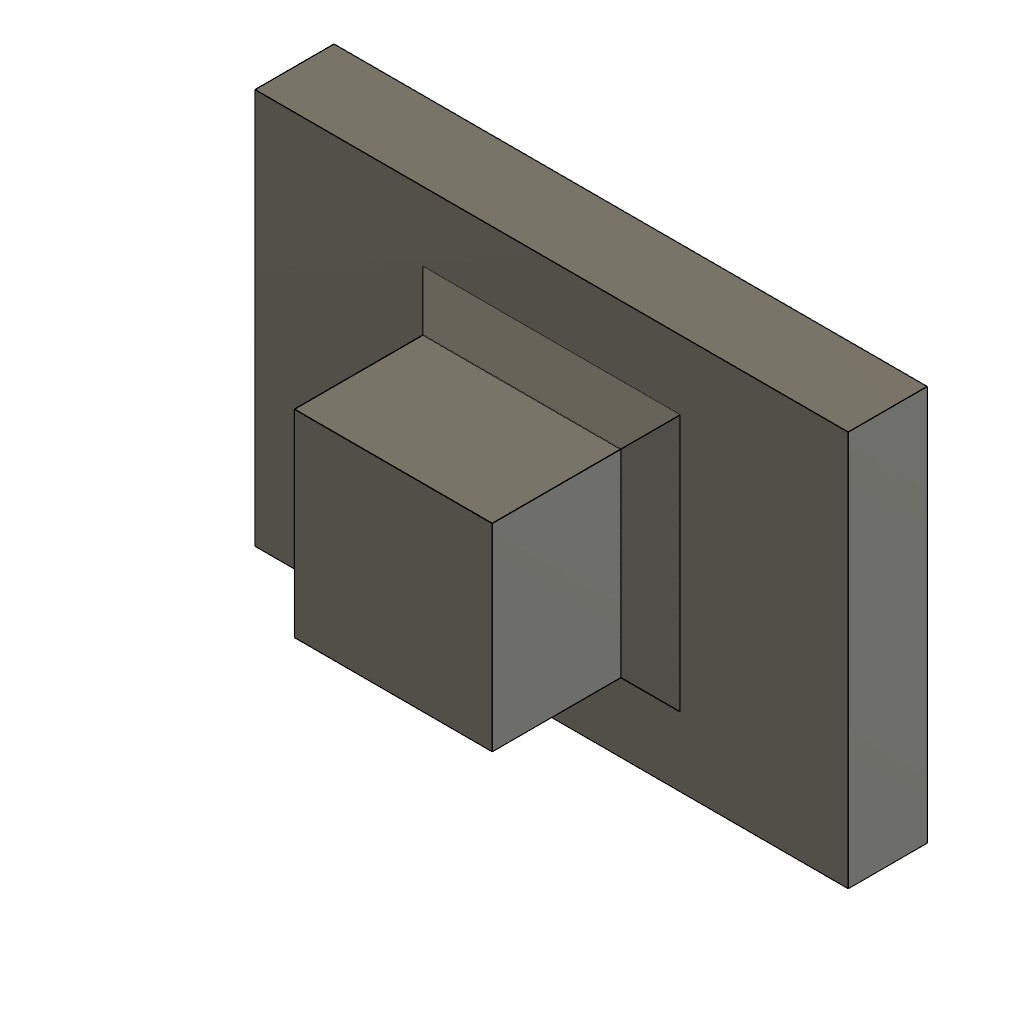
chamfer_concave_boss (Autodesk Fusion 360 design; units mm, degrees)
part number: 2026-11-12-22-57-18-927
Autodesk Fusion 360 part; units mm, degrees
sketch "Sketch1" plane through (0, 0, 0) normal (0, 0, 1) x (1, 0, 0)
  line L0 (0, 0) -> (30, 0)
  line L1 (30, 0) -> (30, 20)
  line L2 (30, 20) -> (0, 20)
  line L3 (0, 20) -> (0, 0)
extrude "Extrude1" add sketch "Sketch1" along normal blind 4
ref_plane "WorkPlane1" through (0, 0, 4) normal (0, 0, 1) x (1, 0, 0)
sketch "Sketch2" plane through (0, 0, 4) normal (0, 0, 1) x (1, 0, 0)
  line L0 (10, 5) -> (20, 5)
  line L1 (20, 5) -> (20, 15)
  line L2 (20, 15) -> (10, 15)
  line L3 (10, 15) -> (10, 5)
extrude "Extrude2" add sketch "Sketch2" along normal blind 8
chamfer "Chamfer1" distance 1.5 angle 45 4 edges at (15, 15, 4) (20, 10, 4) (15, 5, 4) (10, 10, 4) tangent chain off
